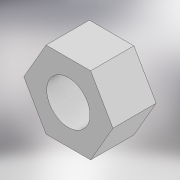
# Autodesk Inventor part: tuerca
Saved by Autodesk Inventor 2021 (Build 250183000, 183)
## iProperties
Created: 2026-06-07
Part Number: tuerca
Material: Genérico
Document SubType Name: Modeling
Designer: thepr
Density: 1 g/cm^3
Appearance: Valor por defecto
Author: thepr
Autodesk Inventor part; units mm, degrees
ref_plane "YZ Plane" through (0, 0, 0) normal (1, 0, 0) x (0, 1, 0)
ref_plane "XZ Plane" through (0, 0, 0) normal (0, 1, 0) x (-1, 0, 0)
ref_plane "XY Plane" through (0, 0, 0) normal (0, 0, 1) x (1, 0, 0)
sketch "Boceto1" plane through (0, 0, 0) normal (0, 0, 1) x (1, 0, 0)
  line L0 (3.0888, 0) -> (1.5444, -2.675)
  line L1 (1.5444, -2.675) -> (-1.5444, -2.675)
  line L2 (-1.5444, -2.675) -> (-3.0888, 0)
  line L3 (-3.0888, 0) -> (-1.5444, 2.675)
  line L4 (-1.5444, 2.675) -> (1.5444, 2.675)
  line L5 (1.5444, 2.675) -> (3.0888, 0)
  circle A0 centre (0, 0) radius 1.5
  dimension "d0" = 5.35
  dimension "d1" = 3
  constraints: 12 end point, 2 coincident, 1 centre point, 1 horizontal, 13 other
  measures "d0" distance between parallel lines of L1 L4
  measures "d1" diameter of A0
extrude "Extrusión1" add sketch "Boceto1" along normal blind 3
